Autodesk Fusion 360 part; units mm, degrees
(part 2 of 2)
sketch "Sketch2" plane through (0, 0, 16.9) normal (0, 0, 1) x (-1, 0, 0)
  circle A0 centre (57.1921, -58) radius 1.75
  circle A1 centre (-33.8079, -58) radius 1.75
  circle A2 centre (-33.8079, 73) radius 1.75
  circle A3 centre (57.1921, 73) radius 1.75
  line L0 (-37.3079, -61.5) -> (60.6921, -61.5)
  line L1 (60.6921, -61.5) -> (60.6921, 76.5)
  line L2 (60.6921, 76.5) -> (-37.3079, 76.5)
  line L3 (-37.3079, 76.5) -> (-37.3079, -61.5)
  line L4 (50.6921, -46) -> (-27.3079, -46)
  arc A4 (-27.3079, -46) -> (-27.3079, -49) centre (-27.3079, -47.5) ccw
  line L5 (-27.3079, -49) -> (50.6921, -49)
  arc A5 (50.6921, -49) -> (50.6921, -46) centre (50.6921, -47.5) ccw
  line L6 (50.6921, -47.5) -> (-27.3079, -47.5) construction
  line L7 (50.6921, -38.1429) -> (-27.3079, -38.1429)
  arc A6 (50.6921, -41.1429) -> (50.6921, -38.1429) centre (50.6921, -39.6429) ccw
  line L8 (-27.3079, -41.1429) -> (50.6921, -41.1429)
  arc A7 (-27.3079, -38.1429) -> (-27.3079, -41.1429) centre (-27.3079, -39.6429) ccw
  line L9 (50.6921, -30.2857) -> (-27.3079, -30.2857)
  arc A8 (50.6921, -33.2857) -> (50.6921, -30.2857) centre (50.6921, -31.7857) ccw
  line L10 (-27.3079, -33.2857) -> (50.6921, -33.2857)
  arc A9 (-27.3079, -30.2857) -> (-27.3079, -33.2857) centre (-27.3079, -31.7857) ccw
  line L11 (50.6921, -22.4286) -> (-27.3079, -22.4286)
  arc A10 (50.6921, -25.4286) -> (50.6921, -22.4286) centre (50.6921, -23.9286) ccw
  line L12 (-27.3079, -25.4286) -> (50.6921, -25.4286)
  arc A11 (-27.3079, -22.4286) -> (-27.3079, -25.4286) centre (-27.3079, -23.9286) ccw
  line L13 (50.6921, -14.5714) -> (-27.3079, -14.5714)
  arc A12 (50.6921, -17.5714) -> (50.6921, -14.5714) centre (50.6921, -16.0714) ccw
  line L14 (-27.3079, -17.5714) -> (50.6921, -17.5714)
  arc A13 (-27.3079, -14.5714) -> (-27.3079, -17.5714) centre (-27.3079, -16.0714) ccw
  line L15 (50.6921, -6.7143) -> (-27.3079, -6.7143)
  arc A14 (50.6921, -9.7143) -> (50.6921, -6.7143) centre (50.6921, -8.2143) ccw
  line L16 (-27.3079, -9.7143) -> (50.6921, -9.7143)
  arc A15 (-27.3079, -6.7143) -> (-27.3079, -9.7143) centre (-27.3079, -8.2143) ccw
  line L17 (50.6921, 1.1429) -> (-27.3079, 1.1429)
  arc A16 (50.6921, -1.8571) -> (50.6921, 1.1429) centre (50.6921, -0.3571) ccw
  line L18 (-27.3079, -1.8571) -> (50.6921, -1.8571)
  arc A17 (-27.3079, 1.1429) -> (-27.3079, -1.8571) centre (-27.3079, -0.3571) ccw
  line L19 (50.6921, 9) -> (-27.3079, 9)
  arc A18 (50.6921, 6) -> (50.6921, 9) centre (50.6921, 7.5) ccw
  line L20 (-27.3079, 6) -> (50.6921, 6)
  arc A19 (-27.3079, 9) -> (-27.3079, 6) centre (-27.3079, 7.5) ccw
  line L21 (50.6921, 16.8571) -> (-27.3079, 16.8571)
  arc A20 (50.6921, 13.8571) -> (50.6921, 16.8571) centre (50.6921, 15.3571) ccw
  line L22 (-27.3079, 13.8571) -> (50.6921, 13.8571)
  arc A21 (-27.3079, 16.8571) -> (-27.3079, 13.8571) centre (-27.3079, 15.3571) ccw
  line L23 (50.6921, 24.7143) -> (-27.3079, 24.7143)
  arc A22 (50.6921, 21.7143) -> (50.6921, 24.7143) centre (50.6921, 23.2143) ccw
  line L24 (-27.3079, 21.7143) -> (50.6921, 21.7143)
  arc A23 (-27.3079, 24.7143) -> (-27.3079, 21.7143) centre (-27.3079, 23.2143) ccw
  line L25 (50.6921, 32.5714) -> (-27.3079, 32.5714)
  arc A24 (50.6921, 29.5714) -> (50.6921, 32.5714) centre (50.6921, 31.0714) ccw
  line L26 (-27.3079, 29.5714) -> (50.6921, 29.5714)
  arc A25 (-27.3079, 32.5714) -> (-27.3079, 29.5714) centre (-27.3079, 31.0714) ccw
  line L27 (50.6921, 40.4286) -> (-27.3079, 40.4286)
  arc A26 (50.6921, 37.4286) -> (50.6921, 40.4286) centre (50.6921, 38.9286) ccw
  line L28 (-27.3079, 37.4286) -> (50.6921, 37.4286)
  arc A27 (-27.3079, 40.4286) -> (-27.3079, 37.4286) centre (-27.3079, 38.9286) ccw
  line L29 (50.6921, 48.2857) -> (-27.3079, 48.2857)
  arc A28 (50.6921, 45.2857) -> (50.6921, 48.2857) centre (50.6921, 46.7857) ccw
  line L30 (-27.3079, 45.2857) -> (50.6921, 45.2857)
  arc A29 (-27.3079, 48.2857) -> (-27.3079, 45.2857) centre (-27.3079, 46.7857) ccw
  line L31 (50.6921, 56.1429) -> (-27.3079, 56.1429)
  arc A30 (50.6921, 53.1429) -> (50.6921, 56.1429) centre (50.6921, 54.6429) ccw
  line L32 (-27.3079, 53.1429) -> (50.6921, 53.1429)
  arc A31 (-27.3079, 56.1429) -> (-27.3079, 53.1429) centre (-27.3079, 54.6429) ccw
  line L33 (50.6921, 64) -> (-27.3079, 64)
  arc A32 (50.6921, 61) -> (50.6921, 64) centre (50.6921, 62.5) ccw
  line L34 (-27.3079, 61) -> (50.6921, 61)
  arc A33 (-27.3079, 64) -> (-27.3079, 61) centre (-27.3079, 62.5) ccw
  dimension "d8" = 3
  dimension "d9" = 10
  dimension "d10" = 10
  dimension "d14" = 0
  dimension "d15" = 110
  dimension "d16" = 12.5
  measures "d8" diameter of A4
  measures "d9" distance of L1 A5.centre
  measures "d10" distance of L3 A4.centre
  measures "d16" distance of L0 L5
extrude "Extrude2" cut sketch "Sketch2" against normal up to surface (1.5 mm away) contours L4 A4 L5 A5 | L7 A6 L8 A7 | L9 A8 L10 A9 | L11 A10 L12 A11 | L13 A12 L14 A13 | L15 A14 L16 A15 | L17 A16 L18 A17 | L19 A18 L20 A19 | L21 A20 L22 A21 | L23 A22 L24 A23 | L25 A24 L26 A25 | L27 A26 L28 A27 | L29 A28 L30 A29 | L31 A30 L32 A31 | L33 A32 L34 A33
